Autodesk Fusion 360 part; units mm, degrees
(part 3 of 28)
  line L1276 (49.3387, 32.3207, -1.4859) -> (49.5252, 32.3813, -1.4859)
  line L1277 (49.5252, 32.3813, -1.4859) -> (49.719, 32.412, -1.4859)
  line L1278 (49.719, 32.412, -1.4859) -> (49.9151, 32.412, -1.4859)
  line L1279 (49.9151, 32.412, -1.4859) -> (50.1088, 32.3813, -1.4859)
  line L1280 (111.0688, 32.3813, -1.4859) -> (111.2554, 32.3207, -1.4859)
  line L1281 (111.2554, 32.3207, -1.4859) -> (111.4302, 32.2316, -1.4859)
  line L1282 (111.4302, 32.2316, -1.4859) -> (111.5888, 32.1163, -1.4859)
  line L1283 (111.5888, 32.1163, -1.4859) -> (111.7275, 31.9776, -1.4859)
  line L1284 (111.7275, 31.9776, -1.4859) -> (111.8428, 31.8189, -1.4859)
  line L1285 (111.8428, 31.8189, -1.4859) -> (111.9319, 31.6442, -1.4859)
  line L1286 (111.9319, 31.6442, -1.4859) -> (111.9925, 31.4576, -1.4859)
  line L1287 (111.9925, 31.4576, -1.4859) -> (112.0232, 31.2639, -1.4859)
  line L1288 (112.0232, 31.2639, -1.4859) -> (112.027, 31.1658, -1.4859)
  line L1289 (112.027, 31.1658, -1.4859) -> (112.027, 30.6658, -1.4859)
  line L1290 (112.027, 30.6658, -1.4859) -> (112.0232, 30.5677, -1.4859)
  line L1291 (112.0232, 30.5677, -1.4859) -> (111.9925, 30.374, -1.4859)
  line L1292 (111.9925, 30.374, -1.4859) -> (111.9319, 30.1875, -1.4859)
  line L1293 (111.9319, 30.1875, -1.4859) -> (111.8428, 30.0127, -1.4859)
  line L1294 (111.8428, 30.0127, -1.4859) -> (111.7275, 29.854, -1.4859)
  line L1295 (111.7275, 29.854, -1.4859) -> (111.5888, 29.7153, -1.4859)
  line L1296 (111.5888, 29.7153, -1.4859) -> (111.4302, 29.6, -1.4859)
  line L1297 (111.4302, 29.6, -1.4859) -> (111.2554, 29.511, -1.4859)
  line L1298 (111.2554, 29.511, -1.4859) -> (111.0688, 29.4504, -1.4859)
  line L1299 (111.0688, 29.4504, -1.4859) -> (110.8751, 29.4197, -1.4859)
  line L1300 (110.8751, 29.4197, -1.4859) -> (110.679, 29.4197, -1.4859)
  line L1301 (110.679, 29.4197, -1.4859) -> (110.4852, 29.4504, -1.4859)
  line L1302 (110.4852, 29.4504, -1.4859) -> (110.2987, 29.511, -1.4859)
  line L1303 (110.2987, 29.511, -1.4859) -> (110.1239, 29.6, -1.4859)
  line L1304 (110.1239, 29.6, -1.4859) -> (109.9652, 29.7153, -1.4859)
  line L1305 (109.9652, 29.7153, -1.4859) -> (109.8265, 29.854, -1.4859)
  line L1306 (109.8265, 29.854, -1.4859) -> (109.7112, 30.0127, -1.4859)
  line L1307 (109.7112, 30.0127, -1.4859) -> (109.6222, 30.1875, -1.4859)
  line L1308 (109.6222, 30.1875, -1.4859) -> (109.5616, 30.374, -1.4859)
  line L1309 (109.5616, 30.374, -1.4859) -> (109.5309, 30.5677, -1.4859)
  line L1310 (109.5309, 30.5677, -1.4859) -> (109.527, 30.6658, -1.4859)
  line L1311 (109.527, 30.6658, -1.4859) -> (109.527, 31.1658, -1.4859)
  line L1312 (109.527, 31.1658, -1.4859) -> (109.5309, 31.2639, -1.4859)
  line L1313 (109.5309, 31.2639, -1.4859) -> (109.5616, 31.4576, -1.4859)
  line L1314 (109.5616, 31.4576, -1.4859) -> (109.6222, 31.6442, -1.4859)
  line L1315 (109.6222, 31.6442, -1.4859) -> (109.7112, 31.8189, -1.4859)
  line L1316 (109.7112, 31.8189, -1.4859) -> (109.8265, 31.9776, -1.4859)
  line L1317 (109.8265, 31.9776, -1.4859) -> (109.9652, 32.1163, -1.4859)
  line L1318 (109.9652, 32.1163, -1.4859) -> (110.1239, 32.2316, -1.4859)
  line L1319 (110.1239, 32.2316, -1.4859) -> (110.2987, 32.3207, -1.4859)
  line L1320 (110.2987, 32.3207, -1.4859) -> (110.4852, 32.3813, -1.4859)
  line L1321 (110.4852, 32.3813, -1.4859) -> (110.679, 32.412, -1.4859)
  line L1322 (110.679, 32.412, -1.4859) -> (110.8751, 32.412, -1.4859)
  line L1323 (110.8751, 32.412, -1.4859) -> (111.0688, 32.3813, -1.4859)
  line L1324 (23.2045, 32.6394, -1.4859) -> (23.3177, 32.5841, -1.4859)
  line L1325 (23.3177, 32.5841, -1.4859) -> (23.4069, 32.4949, -1.4859)
  line L1326 (23.4069, 32.4949, -1.4859) -> (23.4622, 32.3817, -1.4859)
  line L1327 (23.4622, 32.3817, -1.4859) -> (23.4781, 32.2725, -1.4859)
  line L1328 (23.4781, 32.2725, -1.4859) -> (23.4781, 30.5881, -1.4859)
  line L1329 (23.4781, 30.5881, -1.4859) -> (23.4622, 30.4789, -1.4859)
  line L1330 (23.4622, 30.4789, -1.4859) -> (23.4069, 30.3657, -1.4859)
  line L1331 (23.4069, 30.3657, -1.4859) -> (23.3177, 30.2766, -1.4859)
  line L1332 (23.3177, 30.2766, -1.4859) -> (23.2045, 30.2212, -1.4859)
  line L1333 (23.2045, 30.2212, -1.4859) -> (23.0953, 30.2053, -1.4859)
  line L1334 (23.0953, 30.2053, -1.4859) -> (20.8609, 30.2053, -1.4859)
  line L1335 (20.8609, 30.2053, -1.4859) -> (20.7517, 30.2212, -1.4859)
  line L1336 (20.7517, 30.2212, -1.4859) -> (20.6385, 30.2766, -1.4859)
  line L1337 (20.6385, 30.2766, -1.4859) -> (20.5494, 30.3657, -1.4859)
  line L1338 (20.5494, 30.3657, -1.4859) -> (20.494, 30.4789, -1.4859)
  line L1339 (20.494, 30.4789, -1.4859) -> (20.4781, 30.5881, -1.4859)
  line L1340 (20.4781, 30.5881, -1.4859) -> (20.4781, 32.2725, -1.4859)
  line L1341 (20.4781, 32.2725, -1.4859) -> (20.494, 32.3817, -1.4859)
  line L1342 (20.494, 32.3817, -1.4859) -> (20.5494, 32.4949, -1.4859)
  line L1343 (20.5494, 32.4949, -1.4859) -> (20.6385, 32.5841, -1.4859)
  line L1344 (20.6385, 32.5841, -1.4859) -> (20.7517, 32.6394, -1.4859)
  line L1345 (20.7517, 32.6394, -1.4859) -> (20.8609, 32.6553, -1.4859)
  line L1346 (20.8609, 32.6553, -1.4859) -> (23.0953, 32.6553, -1.4859)
  line L1347 (23.0953, 32.6553, -1.4859) -> (23.2045, 32.6394, -1.4859)
  line L1348 (84.1645, 32.6394, -1.4859) -> (84.2777, 32.5841, -1.4859)
  line L1349 (84.2777, 32.5841, -1.4859) -> (84.3669, 32.4949, -1.4859)
  line L1350 (84.3669, 32.4949, -1.4859) -> (84.4222, 32.3817, -1.4859)
  line L1351 (84.4222, 32.3817, -1.4859) -> (84.4381, 32.2725, -1.4859)
  line L1352 (84.4381, 32.2725, -1.4859) -> (84.4381, 30.5881, -1.4859)
  line L1353 (84.4381, 30.5881, -1.4859) -> (84.4222, 30.4789, -1.4859)
  line L1354 (84.4222, 30.4789, -1.4859) -> (84.3669, 30.3657, -1.4859)
  line L1355 (84.3669, 30.3657, -1.4859) -> (84.2777, 30.2766, -1.4859)
  line L1356 (84.2777, 30.2766, -1.4859) -> (84.1645, 30.2212, -1.4859)
  line L1357 (84.1645, 30.2212, -1.4859) -> (84.0553, 30.2053, -1.4859)
  line L1358 (84.0553, 30.2053, -1.4859) -> (81.8209, 30.2053, -1.4859)
  line L1359 (81.8209, 30.2053, -1.4859) -> (81.7117, 30.2212, -1.4859)
  line L1360 (81.7117, 30.2212, -1.4859) -> (81.5985, 30.2766, -1.4859)
  line L1361 (81.5985, 30.2766, -1.4859) -> (81.5094, 30.3657, -1.4859)
  line L1362 (81.5094, 30.3657, -1.4859) -> (81.454, 30.4789, -1.4859)
  line L1363 (81.454, 30.4789, -1.4859) -> (81.4381, 30.5881, -1.4859)
  line L1364 (81.4381, 30.5881, -1.4859) -> (81.4381, 32.2725, -1.4859)
  line L1365 (81.4381, 32.2725, -1.4859) -> (81.454, 32.3817, -1.4859)
  line L1366 (81.454, 32.3817, -1.4859) -> (81.5094, 32.4949, -1.4859)
  line L1367 (81.5094, 32.4949, -1.4859) -> (81.5985, 32.5841, -1.4859)
  line L1368 (81.5985, 32.5841, -1.4859) -> (81.7117, 32.6394, -1.4859)
  line L1369 (81.7117, 32.6394, -1.4859) -> (81.8209, 32.6553, -1.4859)
  line L1370 (81.8209, 32.6553, -1.4859) -> (84.0553, 32.6553, -1.4859)
  line L1371 (84.0553, 32.6553, -1.4859) -> (84.1645, 32.6394, -1.4859)
  line L1372 (10.8949, 32.7554, -1.4859) -> (11.0848, 32.7254, -1.4859)
  line L1373 (11.0848, 32.7254, -1.4859) -> (11.2676, 32.666, -1.4859)
  line L1374 (11.2676, 32.666, -1.4859) -> (11.4389, 32.5787, -1.4859)
  line L1375 (11.4389, 32.5787, -1.4859) -> (11.5944, 32.4657, -1.4859)
  line L1376 (11.5944, 32.4657, -1.4859) -> (11.7303, 32.3298, -1.4859)
  line L1377 (11.7303, 32.3298, -1.4859) -> (11.8433, 32.1743, -1.4859)
  line L1378 (11.8433, 32.1743, -1.4859) -> (11.9306, 32.003, -1.4859)
  line L1379 (11.9306, 32.003, -1.4859) -> (11.99, 31.8202, -1.4859)
  line L1380 (11.99, 31.8202, -1.4859) -> (12.0201, 31.6303, -1.4859)
  line L1381 (12.0201, 31.6303, -1.4859) -> (12.0201, 31.4381, -1.4859)
  line L1382 (12.0201, 31.4381, -1.4859) -> (11.99, 31.2482, -1.4859)
  line L1383 (11.99, 31.2482, -1.4859) -> (11.9306, 31.0654, -1.4859)
  line L1384 (11.9306, 31.0654, -1.4859) -> (11.8433, 30.8941, -1.4859)
  line L1385 (11.8433, 30.8941, -1.4859) -> (11.7303, 30.7386, -1.4859)
  line L1386 (11.7303, 30.7386, -1.4859) -> (11.5944, 30.6027, -1.4859)
  line L1387 (11.5944, 30.6027, -1.4859) -> (11.4389, 30.4897, -1.4859)
  line L1388 (11.4389, 30.4897, -1.4859) -> (11.2676, 30.4024, -1.4859)
  line L1389 (11.2676, 30.4024, -1.4859) -> (11.0848, 30.343, -1.4859)
  line L1390 (11.0848, 30.343, -1.4859) -> (10.8949, 30.313, -1.4859)
  line L1391 (10.8949, 30.313, -1.4859) -> (10.7988, 30.3092, -1.4859)
  line L1392 (10.7988, 30.3092, -1.4859) -> (10.2488, 30.3092, -1.4859)
  line L1393 (10.2488, 30.3092, -1.4859) -> (10.1527, 30.313, -1.4859)
  line L1394 (10.1527, 30.313, -1.4859) -> (9.9629, 30.343, -1.4859)
  line L1395 (9.9629, 30.343, -1.4859) -> (9.7801, 30.4024, -1.4859)
  line L1396 (9.7801, 30.4024, -1.4859) -> (9.6088, 30.4897, -1.4859)
  line L1397 (9.6088, 30.4897, -1.4859) -> (9.4533, 30.6027, -1.4859)
  line L1398 (9.4533, 30.6027, -1.4859) -> (9.3173, 30.7386, -1.4859)
  line L1399 (9.3173, 30.7386, -1.4859) -> (9.2044, 30.8941, -1.4859)
  line L1400 (9.2044, 30.8941, -1.4859) -> (9.1171, 31.0654, -1.4859)
  line L1401 (9.1171, 31.0654, -1.4859) -> (9.0577, 31.2482, -1.4859)
  line L1402 (9.0577, 31.2482, -1.4859) -> (9.0276, 31.4381, -1.4859)
  line L1403 (9.0276, 31.4381, -1.4859) -> (9.0276, 31.6303, -1.4859)
  line L1404 (9.0276, 31.6303, -1.4859) -> (9.0577, 31.8202, -1.4859)
  line L1405 (9.0577, 31.8202, -1.4859) -> (9.1171, 32.003, -1.4859)
  line L1406 (9.1171, 32.003, -1.4859) -> (9.2044, 32.1743, -1.4859)
  line L1407 (9.2044, 32.1743, -1.4859) -> (9.3173, 32.3298, -1.4859)
  line L1408 (9.3173, 32.3298, -1.4859) -> (9.4533, 32.4657, -1.4859)
  line L1409 (9.4533, 32.4657, -1.4859) -> (9.6088, 32.5787, -1.4859)
  line L1410 (9.6088, 32.5787, -1.4859) -> (9.7801, 32.666, -1.4859)
  line L1411 (9.7801, 32.666, -1.4859) -> (9.9629, 32.7254, -1.4859)
  line L1412 (9.9629, 32.7254, -1.4859) -> (10.1527, 32.7554, -1.4859)
  line L1413 (10.1527, 32.7554, -1.4859) -> (10.2488, 32.7592, -1.4859)
  line L1414 (10.2488, 32.7592, -1.4859) -> (10.7988, 32.7592, -1.4859)
  line L1415 (10.7988, 32.7592, -1.4859) -> (10.8949, 32.7554, -1.4859)
  line L1416 (71.8549, 32.7554, -1.4859) -> (72.0448, 32.7254, -1.4859)
  line L1417 (72.0448, 32.7254, -1.4859) -> (72.2276, 32.666, -1.4859)
  line L1418 (72.2276, 32.666, -1.4859) -> (72.3989, 32.5787, -1.4859)
  line L1419 (72.3989, 32.5787, -1.4859) -> (72.5544, 32.4657, -1.4859)
  line L1420 (72.5544, 32.4657, -1.4859) -> (72.6903, 32.3298, -1.4859)
  line L1421 (72.6903, 32.3298, -1.4859) -> (72.8033, 32.1743, -1.4859)
  line L1422 (72.8033, 32.1743, -1.4859) -> (72.8906, 32.003, -1.4859)
  line L1423 (72.8906, 32.003, -1.4859) -> (72.95, 31.8202, -1.4859)
  line L1424 (72.95, 31.8202, -1.4859) -> (72.9801, 31.6303, -1.4859)
  line L1425 (72.9801, 31.6303, -1.4859) -> (72.9801, 31.4381, -1.4859)
  line L1426 (72.9801, 31.4381, -1.4859) -> (72.95, 31.2482, -1.4859)
  line L1427 (72.95, 31.2482, -1.4859) -> (72.8906, 31.0654, -1.4859)
  line L1428 (72.8906, 31.0654, -1.4859) -> (72.8033, 30.8941, -1.4859)
  line L1429 (72.8033, 30.8941, -1.4859) -> (72.6903, 30.7386, -1.4859)
  line L1430 (72.6903, 30.7386, -1.4859) -> (72.5544, 30.6027, -1.4859)
  line L1431 (72.5544, 30.6027, -1.4859) -> (72.3989, 30.4897, -1.4859)
  line L1432 (72.3989, 30.4897, -1.4859) -> (72.2276, 30.4024, -1.4859)
  line L1433 (72.2276, 30.4024, -1.4859) -> (72.0448, 30.343, -1.4859)
  line L1434 (72.0448, 30.343, -1.4859) -> (71.8549, 30.313, -1.4859)
  line L1435 (71.8549, 30.313, -1.4859) -> (71.7588, 30.3092, -1.4859)
  line L1436 (71.7588, 30.3092, -1.4859) -> (71.2088, 30.3092, -1.4859)
  line L1437 (71.2088, 30.3092, -1.4859) -> (71.1127, 30.313, -1.4859)
  line L1438 (71.1127, 30.313, -1.4859) -> (70.9229, 30.343, -1.4859)
  line L1439 (70.9229, 30.343, -1.4859) -> (70.7401, 30.4024, -1.4859)
  line L1440 (70.7401, 30.4024, -1.4859) -> (70.5688, 30.4897, -1.4859)
  line L1441 (70.5688, 30.4897, -1.4859) -> (70.4133, 30.6027, -1.4859)
  line L1442 (70.4133, 30.6027, -1.4859) -> (70.2773, 30.7386, -1.4859)
  line L1443 (70.2773, 30.7386, -1.4859) -> (70.1644, 30.8941, -1.4859)
  line L1444 (70.1644, 30.8941, -1.4859) -> (70.0771, 31.0654, -1.4859)
  line L1445 (70.0771, 31.0654, -1.4859) -> (70.0177, 31.2482, -1.4859)
  line L1446 (70.0177, 31.2482, -1.4859) -> (69.9876, 31.4381, -1.4859)
  line L1447 (69.9876, 31.4381, -1.4859) -> (69.9876, 31.6303, -1.4859)
  line L1448 (69.9876, 31.6303, -1.4859) -> (70.0177, 31.8202, -1.4859)
  line L1449 (70.0177, 31.8202, -1.4859) -> (70.0771, 32.003, -1.4859)
  line L1450 (70.0771, 32.003, -1.4859) -> (70.1644, 32.1743, -1.4859)
  line L1451 (70.1644, 32.1743, -1.4859) -> (70.2773, 32.3298, -1.4859)
  line L1452 (70.2773, 32.3298, -1.4859) -> (70.4133, 32.4657, -1.4859)
  line L1453 (70.4133, 32.4657, -1.4859) -> (70.5688, 32.5787, -1.4859)
  line L1454 (70.5688, 32.5787, -1.4859) -> (70.7401, 32.666, -1.4859)
  line L1455 (70.7401, 32.666, -1.4859) -> (70.9229, 32.7254, -1.4859)
  line L1456 (70.9229, 32.7254, -1.4859) -> (71.1127, 32.7554, -1.4859)
  line L1457 (71.1127, 32.7554, -1.4859) -> (71.2088, 32.7592, -1.4859)
  line L1458 (71.2088, 32.7592, -1.4859) -> (71.7588, 32.7592, -1.4859)
  line L1459 (71.7588, 32.7592, -1.4859) -> (71.8549, 32.7554, -1.4859)
  line L1460 (44.7235, 30.6535, -1.4859) -> (41.5235, 30.6535, -1.4859)
  line L1461 (41.5235, 30.6535, -1.4859) -> (41.5235, 32.6535, -1.4859)
  line L1462 (41.5235, 32.6535, -1.4859) -> (44.7235, 32.6535, -1.4859)
  line L1463 (44.7235, 32.6535, -1.4859) -> (44.7235, 30.6535, -1.4859)
  line L1464 (105.6835, 30.6535, -1.4859) -> (102.4835, 30.6535, -1.4859)
  line L1465 (102.4835, 30.6535, -1.4859) -> (102.4835, 32.6535, -1.4859)
  line L1466 (102.4835, 32.6535, -1.4859) -> (105.6835, 32.6535, -1.4859)
  line L1467 (105.6835, 32.6535, -1.4859) -> (105.6835, 30.6535, -1.4859)
  line L1468 (32.9849, 70.1522, -1.4859) -> (33.1714, 70.0916, -1.4859)
  line L1469 (33.1714, 70.0916, -1.4859) -> (33.3462, 70.0025, -1.4859)
  line L1470 (33.3462, 70.0025, -1.4859) -> (33.5049, 69.8872, -1.4859)
  line L1471 (33.5049, 69.8872, -1.4859) -> (33.6436, 69.7485, -1.4859)
  line L1472 (33.6436, 69.7485, -1.4859) -> (33.7588, 69.5899, -1.4859)
  line L1473 (33.7588, 69.5899, -1.4859) -> (33.8479, 69.4151, -1.4859)
  line L1474 (33.8479, 69.4151, -1.4859) -> (33.9085, 69.2285, -1.4859)
  line L1475 (33.9085, 69.2285, -1.4859) -> (33.9392, 69.0348, -1.4859)
  line L1476 (33.9392, 69.0348, -1.4859) -> (33.943, 68.9367, -1.4859)
  line L1477 (33.943, 68.9367, -1.4859) -> (33.943, 68.4367, -1.4859)
  line L1478 (33.943, 68.4367, -1.4859) -> (33.9392, 68.3387, -1.4859)
  line L1479 (33.9392, 68.3387, -1.4859) -> (33.9085, 68.1449, -1.4859)
  line L1480 (33.9085, 68.1449, -1.4859) -> (33.8479, 67.9584, -1.4859)
  line L1481 (33.8479, 67.9584, -1.4859) -> (33.7588, 67.7836, -1.4859)
  line L1482 (33.7588, 67.7836, -1.4859) -> (33.6436, 67.6249, -1.4859)
  line L1483 (33.6436, 67.6249, -1.4859) -> (33.5049, 67.4862, -1.4859)
  line L1484 (33.5049, 67.4862, -1.4859) -> (33.3462, 67.3709, -1.4859)
  line L1485 (33.3462, 67.3709, -1.4859) -> (33.1714, 67.2819, -1.4859)
  line L1486 (33.1714, 67.2819, -1.4859) -> (32.9848, 67.2213, -1.4859)
  line L1487 (32.9848, 67.2213, -1.4859) -> (32.7911, 67.1906, -1.4859)
  line L1488 (32.7911, 67.1906, -1.4859) -> (32.595, 67.1906, -1.4859)
  line L1489 (32.595, 67.1906, -1.4859) -> (32.4012, 67.2213, -1.4859)
  line L1490 (32.4012, 67.2213, -1.4859) -> (32.2147, 67.2819, -1.4859)
  line L1491 (32.2147, 67.2819, -1.4859) -> (32.163, 67.3082, -1.4859)
  line L1492 (32.163, 67.3082, -1.4859) -> (28.5773, 63.7225, -1.4859)
  line L1493 (28.5773, 63.7225, -1.4859) -> (28.5183, 63.6708, -1.4859)
  line L1494 (28.5183, 63.6708, -1.4859) -> (28.3827, 63.5924, -1.4859)
  line L1495 (28.3827, 63.5924, -1.4859) -> (28.2314, 63.5519, -1.4859)
  line L1496 (28.2314, 63.5519, -1.4859) -> (28.1531, 63.5468, -1.4859)
  line L1497 (28.1531, 63.5468, -1.4859) -> (25.1258, 63.5468, -1.4859)
  line L1498 (25.1258, 63.5468, -1.4859) -> (25.0987, 63.4936, -1.4859)
  line L1499 (25.0987, 63.4936, -1.4859) -> (24.9834, 63.335, -1.4859)
  line L1500 (24.9834, 63.335, -1.4859) -> (24.8447, 63.1963, -1.4859)
  line L1501 (24.8447, 63.1963, -1.4859) -> (24.686, 63.081, -1.4859)
  line L1502 (24.686, 63.081, -1.4859) -> (24.5112, 62.9919, -1.4859)
  line L1503 (24.5112, 62.9919, -1.4859) -> (24.3829, 62.9502, -1.4859)
  line L1504 (24.3829, 62.9502, -1.4859) -> (24.3829, 59.6133, -1.4859)
  line L1505 (24.3829, 59.6133, -1.4859) -> (24.3778, 59.535, -1.4859)
  line L1506 (24.3778, 59.535, -1.4859) -> (24.3372, 59.3837, -1.4859)
  line L1507 (24.3372, 59.3837, -1.4859) -> (24.2589, 59.2481, -1.4859)
  line L1508 (24.2589, 59.2481, -1.4859) -> (24.2072, 59.1891, -1.4859)
  line L1509 (24.2072, 59.1891, -1.4859) -> (20.6569, 55.6388, -1.4859)
  line L1510 (20.6569, 55.6388, -1.4859) -> (20.6569, 46.29, -1.4859)
  line L1511 (20.6569, 46.29, -1.4859) -> (20.6518, 46.2116, -1.4859)
  line L1512 (20.6518, 46.2116, -1.4859) -> (20.6113, 46.0604, -1.4859)
  line L1513 (20.6113, 46.0604, -1.4859) -> (20.5329, 45.9247, -1.4859)
  line L1514 (20.5329, 45.9247, -1.4859) -> (20.4812, 45.8657, -1.4859)
  line L1515 (20.4812, 45.8657, -1.4859) -> (17.2658, 42.6503, -1.4859)
  line L1516 (17.2658, 42.6503, -1.4859) -> (17.2658, 40.7738, -1.4859)
  line L1517 (17.2658, 40.7738, -1.4859) -> (14.8158, 40.7738, -1.4859)
  line L1518 (14.8158, 40.7738, -1.4859) -> (14.8158, 43.7738, -1.4859)
  line L1519 (14.8158, 43.7738, -1.4859) -> (16.6923, 43.7738, -1.4859)
  line L1520 (16.6923, 43.7738, -1.4859) -> (19.4569, 46.5385, -1.4859)
  line L1521 (19.4569, 46.5385, -1.4859) -> (19.4569, 55.8874, -1.4859)
  line L1522 (19.4569, 55.8874, -1.4859) -> (19.4621, 55.9657, -1.4859)
  line L1523 (19.4621, 55.9657, -1.4859) -> (19.5026, 56.117, -1.4859)
  line L1524 (19.5026, 56.117, -1.4859) -> (19.5809, 56.2526, -1.4859)
  line L1525 (19.5809, 56.2526, -1.4859) -> (19.6327, 56.3116, -1.4859)
  line L1526 (19.6327, 56.3116, -1.4859) -> (23.1829, 59.8619, -1.4859)
  line L1527 (23.1829, 59.8619, -1.4859) -> (23.1829, 62.9502, -1.4859)
  line L1528 (23.1829, 62.9502, -1.4859) -> (23.0545, 62.9919, -1.4859)
  line L1529 (23.0545, 62.9919, -1.4859) -> (22.8798, 63.081, -1.4859)
  line L1530 (22.8798, 63.081, -1.4859) -> (22.7211, 63.1963, -1.4859)
  line L1531 (22.7211, 63.1963, -1.4859) -> (22.5824, 63.335, -1.4859)
  line L1532 (22.5824, 63.335, -1.4859) -> (22.4671, 63.4936, -1.4859)
  line L1533 (22.4671, 63.4936, -1.4859) -> (22.378, 63.6684, -1.4859)
  line L1534 (22.378, 63.6684, -1.4859) -> (22.3174, 63.855, -1.4859)
  line L1535 (22.3174, 63.855, -1.4859) -> (22.2867, 64.0487, -1.4859)
  line L1536 (22.2867, 64.0487, -1.4859) -> (22.2867, 64.2448, -1.4859)
  line L1537 (22.2867, 64.2448, -1.4859) -> (22.3174, 64.4386, -1.4859)
  line L1538 (22.3174, 64.4386, -1.4859) -> (22.378, 64.6251, -1.4859)
  line L1539 (22.378, 64.6251, -1.4859) -> (22.4671, 64.7999, -1.4859)
  line L1540 (22.4671, 64.7999, -1.4859) -> (22.5824, 64.9586, -1.4859)
  line L1541 (22.5824, 64.9586, -1.4859) -> (22.7211, 65.0973, -1.4859)
  line L1542 (22.7211, 65.0973, -1.4859) -> (22.8798, 65.2126, -1.4859)
  line L1543 (22.8798, 65.2126, -1.4859) -> (23.0545, 65.3016, -1.4859)
  line L1544 (23.0545, 65.3016, -1.4859) -> (23.2411, 65.3622, -1.4859)
  line L1545 (23.2411, 65.3622, -1.4859) -> (23.4348, 65.3929, -1.4859)
  line L1546 (23.4348, 65.3929, -1.4859) -> (23.5329, 65.3968, -1.4859)
  line L1547 (23.5329, 65.3968, -1.4859) -> (24.0329, 65.3968, -1.4859)
  line L1548 (24.0329, 65.3968, -1.4859) -> (24.131, 65.3929, -1.4859)
  line L1549 (24.131, 65.3929, -1.4859) -> (24.3247, 65.3622, -1.4859)
  line L1550 (24.3247, 65.3622, -1.4859) -> (24.5112, 65.3016, -1.4859)
  line L1551 (24.5112, 65.3016, -1.4859) -> (24.686, 65.2126, -1.4859)
  line L1552 (24.686, 65.2126, -1.4859) -> (24.8447, 65.0973, -1.4859)
  line L1553 (24.8447, 65.0973, -1.4859) -> (24.9834, 64.9586, -1.4859)
  line L1554 (24.9834, 64.9586, -1.4859) -> (25.0987, 64.7999, -1.4859)
  line L1555 (25.0987, 64.7999, -1.4859) -> (25.1258, 64.7468, -1.4859)
  line L1556 (25.1258, 64.7468, -1.4859) -> (27.9045, 64.7468, -1.4859)
  line L1557 (27.9045, 64.7468, -1.4859) -> (31.4537, 68.2959, -1.4859)
  line L1558 (31.4537, 68.2959, -1.4859) -> (31.4469, 68.3387, -1.4859)
  line L1559 (31.4469, 68.3387, -1.4859) -> (31.443, 68.4367, -1.4859)
  line L1560 (31.443, 68.4367, -1.4859) -> (31.443, 68.9367, -1.4859)
  line L1561 (31.443, 68.9367, -1.4859) -> (31.4469, 69.0348, -1.4859)
  line L1562 (31.4469, 69.0348, -1.4859) -> (31.4776, 69.2285, -1.4859)
  line L1563 (31.4776, 69.2285, -1.4859) -> (31.5382, 69.4151, -1.4859)
  line L1564 (31.5382, 69.4151, -1.4859) -> (31.6272, 69.5899, -1.4859)
  line L1565 (31.6272, 69.5899, -1.4859) -> (31.7425, 69.7485, -1.4859)
  line L1566 (31.7425, 69.7485, -1.4859) -> (31.8812, 69.8872, -1.4859)
  line L1567 (31.8812, 69.8872, -1.4859) -> (32.0399, 70.0025, -1.4859)
  line L1568 (32.0399, 70.0025, -1.4859) -> (32.2147, 70.0916, -1.4859)
  line L1569 (32.2147, 70.0916, -1.4859) -> (32.4012, 70.1522, -1.4859)
  line L1570 (32.4012, 70.1522, -1.4859) -> (32.595, 70.1829, -1.4859)
  line L1571 (32.595, 70.1829, -1.4859) -> (32.7911, 70.1829, -1.4859)
  line L1572 (32.7911, 70.1829, -1.4859) -> (32.9848, 70.1522, -1.4859)
  line L1573 (67.9098, 70.1522, -1.4859) -> (68.0964, 70.0916, -1.4859)
  line L1574 (68.0964, 70.0916, -1.4859) -> (68.2712, 70.0025, -1.4859)
  line L1575 (68.2712, 70.0025, -1.4859) -> (68.4299, 69.8872, -1.4859)
  line L1576 (68.4299, 69.8872, -1.4859) -> (68.5686, 69.7485, -1.4859)
  line L1577 (68.5685, 69.7485, -1.4859) -> (68.6838, 69.5899, -1.4859)
  line L1578 (68.6838, 69.5899, -1.4859) -> (68.7729, 69.4151, -1.4859)
  line L1579 (68.7729, 69.4151, -1.4859) -> (68.8335, 69.2285, -1.4859)
  line L1580 (68.8335, 69.2285, -1.4859) -> (68.8642, 69.0348, -1.4859)
  line L1581 (68.8642, 69.0348, -1.4859) -> (68.868, 68.9367, -1.4859)
  line L1582 (68.868, 68.9367, -1.4859) -> (68.868, 68.4367, -1.4859)
  line L1583 (68.868, 68.4367, -1.4859) -> (68.8642, 68.3387, -1.4859)
  line L1584 (68.8642, 68.3387, -1.4859) -> (68.8335, 68.1449, -1.4859)
  line L1585 (68.8335, 68.1449, -1.4859) -> (68.7729, 67.9584, -1.4859)
  line L1586 (68.7729, 67.9584, -1.4859) -> (68.6838, 67.7836, -1.4859)
  line L1587 (68.6838, 67.7836, -1.4859) -> (68.5686, 67.6249, -1.4859)
  line L1588 (68.5685, 67.6249, -1.4859) -> (68.4299, 67.4862, -1.4859)
  line L1589 (68.4299, 67.4862, -1.4859) -> (68.2712, 67.3709, -1.4859)
  line L1590 (68.2712, 67.3709, -1.4859) -> (68.0964, 67.2819, -1.4859)
  line L1591 (68.0964, 67.2819, -1.4859) -> (67.9099, 67.2213, -1.4859)
  line L1592 (67.9098, 67.2213, -1.4859) -> (67.7161, 67.1906, -1.4859)
  line L1593 (67.7161, 67.1906, -1.4859) -> (67.52, 67.1906, -1.4859)
  line L1594 (67.52, 67.1906, -1.4859) -> (67.3262, 67.2213, -1.4859)
  line L1595 (67.3262, 67.2213, -1.4859) -> (67.1397, 67.2819, -1.4859)
  line L1596 (67.1397, 67.2819, -1.4859) -> (67.088, 67.3082, -1.4859)
  line L1597 (67.088, 67.3082, -1.4859) -> (63.5023, 63.7225, -1.4859)
  line L1598 (63.5023, 63.7225, -1.4859) -> (63.4433, 63.6708, -1.4859)
  line L1599 (63.4433, 63.6708, -1.4859) -> (63.3077, 63.5924, -1.4859)
  line L1600 (63.3077, 63.5924, -1.4859) -> (63.1564, 63.5519, -1.4859)
  line L1601 (63.1564, 63.5519, -1.4859) -> (63.0781, 63.5468, -1.4859)
  line L1602 (63.0781, 63.5468, -1.4859) -> (60.0508, 63.5468, -1.4859)
  line L1603 (60.0508, 63.5468, -1.4859) -> (60.0237, 63.4936, -1.4859)
  line L1604 (60.0237, 63.4936, -1.4859) -> (59.9084, 63.335, -1.4859)
  line L1605 (59.9084, 63.335, -1.4859) -> (59.7697, 63.1963, -1.4859)
  line L1606 (59.7697, 63.1963, -1.4859) -> (59.611, 63.081, -1.4859)
  line L1607 (59.611, 63.081, -1.4859) -> (59.4362, 62.9919, -1.4859)
  line L1608 (59.4362, 62.9919, -1.4859) -> (59.3079, 62.9502, -1.4859)
  line L1609 (59.3079, 62.9502, -1.4859) -> (59.3079, 59.6133, -1.4859)
  line L1610 (59.3079, 59.6133, -1.4859) -> (59.3028, 59.535, -1.4859)
  line L1611 (59.3028, 59.535, -1.4859) -> (59.2622, 59.3837, -1.4859)
  line L1612 (59.2622, 59.3837, -1.4859) -> (59.1839, 59.2481, -1.4859)
  line L1613 (59.1839, 59.2481, -1.4859) -> (59.1322, 59.1891, -1.4859)
  line L1614 (59.1322, 59.1891, -1.4859) -> (55.5819, 55.6388, -1.4859)
  line L1615 (55.5819, 55.6388, -1.4859) -> (55.5819, 46.29, -1.4859)
  line L1616 (55.5819, 46.29, -1.4859) -> (55.5768, 46.2116, -1.4859)
  line L1617 (55.5768, 46.2116, -1.4859) -> (55.5363, 46.0604, -1.4859)
  line L1618 (55.5363, 46.0604, -1.4859) -> (55.4579, 45.9247, -1.4859)
  line L1619 (55.4579, 45.9247, -1.4859) -> (55.4062, 45.8657, -1.4859)
  line L1620 (55.4062, 45.8657, -1.4859) -> (52.1908, 42.6503, -1.4859)
  line L1621 (52.1908, 42.6503, -1.4859) -> (52.1908, 40.7738, -1.4859)
  line L1622 (52.1908, 40.7738, -1.4859) -> (49.7408, 40.7738, -1.4859)
  line L1623 (49.7408, 40.7738, -1.4859) -> (49.7408, 43.7738, -1.4859)
  line L1624 (49.7408, 43.7738, -1.4859) -> (51.6173, 43.7738, -1.4859)
  line L1625 (51.6173, 43.7738, -1.4859) -> (54.3819, 46.5385, -1.4859)
  line L1626 (54.3819, 46.5385, -1.4859) -> (54.3819, 55.8874, -1.4859)
  line L1627 (54.3819, 55.8874, -1.4859) -> (54.3871, 55.9657, -1.4859)
  line L1628 (54.3871, 55.9657, -1.4859) -> (54.4276, 56.117, -1.4859)
  line L1629 (54.4276, 56.117, -1.4859) -> (54.5059, 56.2526, -1.4859)
  line L1630 (54.5059, 56.2526, -1.4859) -> (54.5577, 56.3116, -1.4859)
  line L1631 (54.5577, 56.3116, -1.4859) -> (58.1079, 59.8619, -1.4859)
  line L1632 (58.1079, 59.8619, -1.4859) -> (58.1079, 62.9502, -1.4859)
  line L1633 (58.1079, 62.9502, -1.4859) -> (57.9795, 62.9919, -1.4859)
  line L1634 (57.9795, 62.9919, -1.4859) -> (57.8048, 63.081, -1.4859)
  line L1635 (57.8048, 63.081, -1.4859) -> (57.6461, 63.1963, -1.4859)
  line L1636 (57.6461, 63.1963, -1.4859) -> (57.5074, 63.335, -1.4859)
  line L1637 (57.5074, 63.335, -1.4859) -> (57.3921, 63.4936, -1.4859)
  line L1638 (57.3921, 63.4936, -1.4859) -> (57.303, 63.6684, -1.4859)
  line L1639 (57.303, 63.6684, -1.4859) -> (57.2424, 63.855, -1.4859)
  line L1640 (57.2424, 63.855, -1.4859) -> (57.2117, 64.0487, -1.4859)
  line L1641 (57.2117, 64.0487, -1.4859) -> (57.2117, 64.2448, -1.4859)
  line L1642 (57.2117, 64.2448, -1.4859) -> (57.2424, 64.4386, -1.4859)
  line L1643 (57.2424, 64.4386, -1.4859) -> (57.303, 64.6251, -1.4859)
  line L1644 (57.303, 64.6251, -1.4859) -> (57.3921, 64.7999, -1.4859)
  line L1645 (57.3921, 64.7999, -1.4859) -> (57.5074, 64.9586, -1.4859)
  line L1646 (57.5074, 64.9586, -1.4859) -> (57.6461, 65.0973, -1.4859)
  line L1647 (57.6461, 65.0973, -1.4859) -> (57.8048, 65.2126, -1.4859)
  line L1648 (57.8048, 65.2126, -1.4859) -> (57.9795, 65.3016, -1.4859)
  line L1649 (57.9795, 65.3016, -1.4859) -> (58.1661, 65.3622, -1.4859)
  line L1650 (58.1661, 65.3622, -1.4859) -> (58.3598, 65.3929, -1.4859)
  line L1651 (58.3598, 65.3929, -1.4859) -> (58.4579, 65.3968, -1.4859)
  line L1652 (58.4579, 65.3968, -1.4859) -> (58.9579, 65.3968, -1.4859)
  line L1653 (58.9579, 65.3968, -1.4859) -> (59.056, 65.3929, -1.4859)
  line L1654 (59.056, 65.3929, -1.4859) -> (59.2497, 65.3622, -1.4859)
  line L1655 (59.2497, 65.3622, -1.4859) -> (59.4362, 65.3016, -1.4859)
  line L1656 (59.4362, 65.3016, -1.4859) -> (59.611, 65.2126, -1.4859)
  line L1657 (59.611, 65.2126, -1.4859) -> (59.7697, 65.0973, -1.4859)
  line L1658 (59.7697, 65.0973, -1.4859) -> (59.9084, 64.9586, -1.4859)
  line L1659 (59.9084, 64.9586, -1.4859) -> (60.0237, 64.7999, -1.4859)
  line L1660 (60.0237, 64.7999, -1.4859) -> (60.0508, 64.7468, -1.4859)
  line L1661 (60.0508, 64.7468, -1.4859) -> (62.8295, 64.7468, -1.4859)
  line L1662 (62.8295, 64.7468, -1.4859) -> (66.3787, 68.2959, -1.4859)
  line L1663 (66.3787, 68.2959, -1.4859) -> (66.3719, 68.3387, -1.4859)
  line L1664 (66.3719, 68.3387, -1.4859) -> (66.368, 68.4367, -1.4859)
  line L1665 (66.368, 68.4367, -1.4859) -> (66.368, 68.9367, -1.4859)
  line L1666 (66.368, 68.9367, -1.4859) -> (66.3719, 69.0348, -1.4859)
  line L1667 (66.3719, 69.0348, -1.4859) -> (66.4026, 69.2285, -1.4859)
  line L1668 (66.4026, 69.2285, -1.4859) -> (66.4632, 69.4151, -1.4859)
  line L1669 (66.4632, 69.4151, -1.4859) -> (66.5522, 69.5899, -1.4859)
  line L1670 (66.5522, 69.5899, -1.4859) -> (66.6675, 69.7485, -1.4859)
  line L1671 (66.6675, 69.7485, -1.4859) -> (66.8062, 69.8872, -1.4859)
  line L1672 (66.8062, 69.8872, -1.4859) -> (66.9649, 70.0025, -1.4859)
  line L1673 (66.9649, 70.0025, -1.4859) -> (67.1397, 70.0916, -1.4859)
  line L1674 (67.1397, 70.0916, -1.4859) -> (67.3262, 70.1522, -1.4859)
  line L1675 (67.3262, 70.1522, -1.4859) -> (67.52, 70.1829, -1.4859)
  line L1676 (67.52, 70.1829, -1.4859) -> (67.7161, 70.1829, -1.4859)
  line L1677 (67.7161, 70.1829, -1.4859) -> (67.9098, 70.1522, -1.4859)
  line L1678 (102.8349, 70.1522, -1.4859) -> (103.0214, 70.0916, -1.4859)
  line L1679 (103.0214, 70.0916, -1.4859) -> (103.1962, 70.0025, -1.4859)
  line L1680 (103.1962, 70.0025, -1.4859) -> (103.3549, 69.8872, -1.4859)
  line L1681 (103.3549, 69.8872, -1.4859) -> (103.4936, 69.7485, -1.4859)
  line L1682 (103.4936, 69.7485, -1.4859) -> (103.6088, 69.5899, -1.4859)
  line L1683 (103.6088, 69.5899, -1.4859) -> (103.6979, 69.4151, -1.4859)
  line L1684 (103.6979, 69.4151, -1.4859) -> (103.7585, 69.2285, -1.4859)
  line L1685 (103.7585, 69.2285, -1.4859) -> (103.7892, 69.0348, -1.4859)
  line L1686 (103.7892, 69.0348, -1.4859) -> (103.793, 68.9367, -1.4859)
  line L1687 (103.793, 68.9367, -1.4859) -> (103.793, 68.4367, -1.4859)
  line L1688 (103.793, 68.4367, -1.4859) -> (103.7892, 68.3387, -1.4859)
  line L1689 (103.7892, 68.3387, -1.4859) -> (103.7585, 68.1449, -1.4859)
  line L1690 (103.7585, 68.1449, -1.4859) -> (103.6979, 67.9584, -1.4859)
  line L1691 (103.6979, 67.9584, -1.4859) -> (103.6088, 67.7836, -1.4859)
  line L1692 (103.6088, 67.7836, -1.4859) -> (103.4936, 67.6249, -1.4859)
  line L1693 (103.4936, 67.6249, -1.4859) -> (103.3549, 67.4862, -1.4859)
  line L1694 (103.3549, 67.4862, -1.4859) -> (103.1962, 67.3709, -1.4859)
  line L1695 (103.1962, 67.3709, -1.4859) -> (103.0214, 67.2819, -1.4859)
  line L1696 (103.0214, 67.2819, -1.4859) -> (102.8349, 67.2213, -1.4859)
  line L1697 (102.8349, 67.2213, -1.4859) -> (102.6411, 67.1906, -1.4859)
  line L1698 (102.6411, 67.1906, -1.4859) -> (102.445, 67.1906, -1.4859)
  line L1699 (102.445, 67.1906, -1.4859) -> (102.2512, 67.2213, -1.4859)
  line L1700 (102.2512, 67.2213, -1.4859) -> (102.0647, 67.2819, -1.4859)
  line L1701 (102.0647, 67.2819, -1.4859) -> (102.013, 67.3082, -1.4859)
  line L1702 (102.013, 67.3082, -1.4859) -> (98.4273, 63.7225, -1.4859)
  line L1703 (98.4273, 63.7225, -1.4859) -> (98.3683, 63.6708, -1.4859)
  line L1704 (98.3683, 63.6708, -1.4859) -> (98.2327, 63.5924, -1.4859)
  line L1705 (98.2327, 63.5924, -1.4859) -> (98.0814, 63.5519, -1.4859)
  line L1706 (98.0814, 63.5519, -1.4859) -> (98.0031, 63.5468, -1.4859)
  line L1707 (98.0031, 63.5468, -1.4859) -> (94.9758, 63.5468, -1.4859)
  line L1708 (94.9758, 63.5468, -1.4859) -> (94.9487, 63.4936, -1.4859)
  line L1709 (94.9487, 63.4936, -1.4859) -> (94.8334, 63.335, -1.4859)
  line L1710 (94.8334, 63.335, -1.4859) -> (94.6947, 63.1963, -1.4859)
  line L1711 (94.6947, 63.1963, -1.4859) -> (94.536, 63.081, -1.4859)
  line L1712 (94.536, 63.081, -1.4859) -> (94.3612, 62.9919, -1.4859)
  line L1713 (94.3612, 62.9919, -1.4859) -> (94.2329, 62.9502, -1.4859)
  line L1714 (94.2329, 62.9502, -1.4859) -> (94.2329, 59.6133, -1.4859)
  line L1715 (94.2329, 59.6133, -1.4859) -> (94.2278, 59.535, -1.4859)
  line L1716 (94.2278, 59.535, -1.4859) -> (94.1872, 59.3837, -1.4859)
  line L1717 (94.1872, 59.3837, -1.4859) -> (94.1089, 59.2481, -1.4859)
  line L1718 (94.1089, 59.2481, -1.4859) -> (94.0572, 59.1891, -1.4859)
  line L1719 (94.0572, 59.1891, -1.4859) -> (90.5069, 55.6388, -1.4859)
  line L1720 (90.5069, 55.6388, -1.4859) -> (90.5069, 46.29, -1.4859)
  line L1721 (90.5069, 46.29, -1.4859) -> (90.5018, 46.2116, -1.4859)
  line L1722 (90.5018, 46.2116, -1.4859) -> (90.4613, 46.0604, -1.4859)
  line L1723 (90.4613, 46.0604, -1.4859) -> (90.3829, 45.9247, -1.4859)
  line L1724 (90.3829, 45.9247, -1.4859) -> (90.3312, 45.8657, -1.4859)
  line L1725 (90.3312, 45.8657, -1.4859) -> (87.1158, 42.6503, -1.4859)
  line L1726 (87.1158, 42.6503, -1.4859) -> (87.1158, 40.7738, -1.4859)
  line L1727 (87.1158, 40.7738, -1.4859) -> (84.6658, 40.7738, -1.4859)
  line L1728 (84.6658, 40.7738, -1.4859) -> (84.6658, 43.7738, -1.4859)
  line L1729 (84.6658, 43.7738, -1.4859) -> (86.5423, 43.7738, -1.4859)
  line L1730 (86.5423, 43.7738, -1.4859) -> (89.3069, 46.5385, -1.4859)
  line L1731 (89.3069, 46.5385, -1.4859) -> (89.3069, 55.8874, -1.4859)
  line L1732 (89.3069, 55.8874, -1.4859) -> (89.3121, 55.9657, -1.4859)
  line L1733 (89.3121, 55.9657, -1.4859) -> (89.3526, 56.117, -1.4859)
  line L1734 (89.3526, 56.117, -1.4859) -> (89.4309, 56.2526, -1.4859)
  line L1735 (89.4309, 56.2526, -1.4859) -> (89.4827, 56.3116, -1.4859)
  line L1736 (89.4827, 56.3116, -1.4859) -> (93.0329, 59.8619, -1.4859)
  line L1737 (93.0329, 59.8619, -1.4859) -> (93.0329, 62.9502, -1.4859)
  line L1738 (93.0329, 62.9502, -1.4859) -> (92.9045, 62.9919, -1.4859)
  line L1739 (92.9045, 62.9919, -1.4859) -> (92.7298, 63.081, -1.4859)
  line L1740 (92.7298, 63.081, -1.4859) -> (92.5711, 63.1963, -1.4859)
  line L1741 (92.5711, 63.1963, -1.4859) -> (92.4324, 63.335, -1.4859)
  line L1742 (92.4324, 63.335, -1.4859) -> (92.3171, 63.4936, -1.4859)
  line L1743 (92.3171, 63.4936, -1.4859) -> (92.228, 63.6684, -1.4859)
  line L1744 (92.228, 63.6684, -1.4859) -> (92.1674, 63.855, -1.4859)
  line L1745 (92.1674, 63.855, -1.4859) -> (92.1367, 64.0487, -1.4859)
  line L1746 (92.1367, 64.0487, -1.4859) -> (92.1367, 64.2448, -1.4859)
  line L1747 (92.1367, 64.2448, -1.4859) -> (92.1674, 64.4386, -1.4859)
  line L1748 (92.1674, 64.4386, -1.4859) -> (92.228, 64.6251, -1.4859)
  line L1749 (92.228, 64.6251, -1.4859) -> (92.3171, 64.7999, -1.4859)
  line L1750 (92.3171, 64.7999, -1.4859) -> (92.4324, 64.9586, -1.4859)
  line L1751 (92.4324, 64.9586, -1.4859) -> (92.5711, 65.0973, -1.4859)
  line L1752 (92.5711, 65.0973, -1.4859) -> (92.7298, 65.2126, -1.4859)
  line L1753 (92.7298, 65.2126, -1.4859) -> (92.9045, 65.3016, -1.4859)
  line L1754 (92.9045, 65.3016, -1.4859) -> (93.0911, 65.3622, -1.4859)
  line L1755 (93.0911, 65.3622, -1.4859) -> (93.2848, 65.3929, -1.4859)
  line L1756 (93.2848, 65.3929, -1.4859) -> (93.3829, 65.3968, -1.4859)
  line L1757 (93.3829, 65.3968, -1.4859) -> (93.8829, 65.3968, -1.4859)
  line L1758 (93.8829, 65.3968, -1.4859) -> (93.981, 65.3929, -1.4859)
  line L1759 (93.981, 65.3929, -1.4859) -> (94.1747, 65.3622, -1.4859)
  line L1760 (94.1747, 65.3622, -1.4859) -> (94.3612, 65.3016, -1.4859)
  line L1761 (94.3612, 65.3016, -1.4859) -> (94.536, 65.2126, -1.4859)
  line L1762 (94.536, 65.2126, -1.4859) -> (94.6947, 65.0973, -1.4859)
  line L1763 (94.6947, 65.0973, -1.4859) -> (94.8334, 64.9586, -1.4859)
  line L1764 (94.8334, 64.9586, -1.4859) -> (94.9487, 64.7999, -1.4859)
  line L1765 (94.9487, 64.7999, -1.4859) -> (94.9758, 64.7468, -1.4859)
  line L1766 (94.9758, 64.7468, -1.4859) -> (97.7545, 64.7468, -1.4859)
  line L1767 (97.7545, 64.7468, -1.4859) -> (101.3037, 68.2959, -1.4859)
  line L1768 (101.3037, 68.2959, -1.4859) -> (101.2969, 68.3387, -1.4859)
  line L1769 (101.2969, 68.3387, -1.4859) -> (101.293, 68.4367, -1.4859)
  line L1770 (101.293, 68.4367, -1.4859) -> (101.293, 68.9367, -1.4859)
  line L1771 (101.293, 68.9367, -1.4859) -> (101.2969, 69.0348, -1.4859)
  line L1772 (101.2969, 69.0348, -1.4859) -> (101.3276, 69.2285, -1.4859)
  line L1773 (101.3276, 69.2285, -1.4859) -> (101.3882, 69.4151, -1.4859)
  line L1774 (101.3882, 69.4151, -1.4859) -> (101.4772, 69.5899, -1.4859)
  line L1775 (101.4772, 69.5899, -1.4859) -> (101.5925, 69.7485, -1.4859)
  line L1776 (101.5925, 69.7485, -1.4859) -> (101.7312, 69.8872, -1.4859)
  line L1777 (101.7312, 69.8872, -1.4859) -> (101.8899, 70.0025, -1.4859)
  line L1778 (101.8899, 70.0025, -1.4859) -> (102.0647, 70.0916, -1.4859)
  line L1779 (102.0647, 70.0916, -1.4859) -> (102.2512, 70.1522, -1.4859)
  line L1780 (102.2512, 70.1522, -1.4859) -> (102.445, 70.1829, -1.4859)
  line L1781 (102.445, 70.1829, -1.4859) -> (102.6411, 70.1829, -1.4859)
  line L1782 (102.6411, 70.1829, -1.4859) -> (102.8349, 70.1522, -1.4859)
  line L1783 (137.7599, 70.1522, -1.4859) -> (137.9464, 70.0916, -1.4859)
  line L1784 (137.9464, 70.0916, -1.4859) -> (138.1212, 70.0025, -1.4859)
  line L1785 (138.1212, 70.0025, -1.4859) -> (138.2799, 69.8872, -1.4859)
  line L1786 (138.2799, 69.8872, -1.4859) -> (138.4186, 69.7485, -1.4859)
  line L1787 (138.4186, 69.7485, -1.4859) -> (138.5338, 69.5899, -1.4859)
  line L1788 (138.5338, 69.5899, -1.4859) -> (138.6229, 69.4151, -1.4859)
  line L1789 (138.6229, 69.4151, -1.4859) -> (138.6835, 69.2285, -1.4859)
  line L1790 (138.6835, 69.2285, -1.4859) -> (138.7142, 69.0348, -1.4859)
  line L1791 (138.7142, 69.0348, -1.4859) -> (138.718, 68.9367, -1.4859)
  line L1792 (138.718, 68.9367, -1.4859) -> (138.718, 68.4367, -1.4859)
  line L1793 (138.718, 68.4367, -1.4859) -> (138.7142, 68.3387, -1.4859)
  line L1794 (138.7142, 68.3387, -1.4859) -> (138.6835, 68.1449, -1.4859)
  line L1795 (138.6835, 68.1449, -1.4859) -> (138.6229, 67.9584, -1.4859)
  line L1796 (138.6229, 67.9584, -1.4859) -> (138.5338, 67.7836, -1.4859)
  line L1797 (138.5338, 67.7836, -1.4859) -> (138.4186, 67.6249, -1.4859)
  line L1798 (138.4186, 67.6249, -1.4859) -> (138.2799, 67.4862, -1.4859)
  line L1799 (138.2799, 67.4862, -1.4859) -> (138.1212, 67.3709, -1.4859)
  line L1800 (138.1212, 67.3709, -1.4859) -> (137.9464, 67.2819, -1.4859)
  line L1801 (137.9464, 67.2819, -1.4859) -> (137.7599, 67.2213, -1.4859)
  line L1802 (137.7599, 67.2213, -1.4859) -> (137.5661, 67.1906, -1.4859)
  line L1803 (137.5661, 67.1906, -1.4859) -> (137.37, 67.1906, -1.4859)
  line L1804 (137.37, 67.1906, -1.4859) -> (137.1762, 67.2213, -1.4859)
  line L1805 (137.1762, 67.2213, -1.4859) -> (136.9897, 67.2819, -1.4859)
  line L1806 (136.9897, 67.2819, -1.4859) -> (136.938, 67.3082, -1.4859)
  line L1807 (136.938, 67.3082, -1.4859) -> (133.3523, 63.7225, -1.4859)
  line L1808 (133.3523, 63.7225, -1.4859) -> (133.2933, 63.6708, -1.4859)
  line L1809 (133.2933, 63.6708, -1.4859) -> (133.1577, 63.5924, -1.4859)
  line L1810 (133.1577, 63.5924, -1.4859) -> (133.0064, 63.5519, -1.4859)
  line L1811 (133.0064, 63.5519, -1.4859) -> (132.9281, 63.5468, -1.4859)
  line L1812 (132.9281, 63.5468, -1.4859) -> (129.9008, 63.5468, -1.4859)
  line L1813 (129.9008, 63.5468, -1.4859) -> (129.8737, 63.4936, -1.4859)
  line L1814 (129.8737, 63.4936, -1.4859) -> (129.7584, 63.335, -1.4859)
  line L1815 (129.7584, 63.335, -1.4859) -> (129.6197, 63.1963, -1.4859)
  line L1816 (129.6197, 63.1963, -1.4859) -> (129.461, 63.081, -1.4859)
  line L1817 (129.461, 63.081, -1.4859) -> (129.2862, 62.9919, -1.4859)
  line L1818 (129.2862, 62.9919, -1.4859) -> (129.1579, 62.9502, -1.4859)
  line L1819 (129.1579, 62.9502, -1.4859) -> (129.1579, 59.6133, -1.4859)
  line L1820 (129.1579, 59.6133, -1.4859) -> (129.1528, 59.535, -1.4859)
  line L1821 (129.1528, 59.535, -1.4859) -> (129.1122, 59.3837, -1.4859)
  line L1822 (129.1122, 59.3837, -1.4859) -> (129.0339, 59.2481, -1.4859)
  line L1823 (129.0339, 59.2481, -1.4859) -> (128.9822, 59.1891, -1.4859)
  line L1824 (128.9822, 59.1891, -1.4859) -> (125.4319, 55.6388, -1.4859)
  line L1825 (125.4319, 55.6388, -1.4859) -> (125.4319, 46.29, -1.4859)
  line L1826 (125.4319, 46.29, -1.4859) -> (125.4268, 46.2116, -1.4859)
  line L1827 (125.4268, 46.2116, -1.4859) -> (125.3863, 46.0604, -1.4859)
  line L1828 (125.3863, 46.0604, -1.4859) -> (125.3079, 45.9247, -1.4859)
  line L1829 (125.3079, 45.9247, -1.4859) -> (125.2562, 45.8657, -1.4859)
  line L1830 (125.2562, 45.8657, -1.4859) -> (122.0408, 42.6503, -1.4859)
  line L1831 (122.0408, 42.6503, -1.4859) -> (122.0408, 40.7738, -1.4859)
  line L1832 (122.0408, 40.7738, -1.4859) -> (119.5908, 40.7738, -1.4859)
  line L1833 (119.5908, 40.7738, -1.4859) -> (119.5908, 43.7738, -1.4859)
  line L1834 (119.5908, 43.7738, -1.4859) -> (121.4673, 43.7738, -1.4859)
  line L1835 (121.4673, 43.7738, -1.4859) -> (124.2319, 46.5385, -1.4859)
  line L1836 (124.2319, 46.5385, -1.4859) -> (124.2319, 55.8874, -1.4859)
  line L1837 (124.2319, 55.8874, -1.4859) -> (124.2371, 55.9657, -1.4859)
  line L1838 (124.2371, 55.9657, -1.4859) -> (124.2776, 56.117, -1.4859)
  line L1839 (124.2776, 56.117, -1.4859) -> (124.3559, 56.2526, -1.4859)
  line L1840 (124.3559, 56.2526, -1.4859) -> (124.4077, 56.3116, -1.4859)
  line L1841 (124.4077, 56.3116, -1.4859) -> (127.9579, 59.8619, -1.4859)
  line L1842 (127.9579, 59.8619, -1.4859) -> (127.9579, 62.9502, -1.4859)
  line L1843 (127.9579, 62.9502, -1.4859) -> (127.8295, 62.9919, -1.4859)
  line L1844 (127.8295, 62.9919, -1.4859) -> (127.6548, 63.081, -1.4859)
  line L1845 (127.6548, 63.081, -1.4859) -> (127.4961, 63.1963, -1.4859)
  line L1846 (127.4961, 63.1963, -1.4859) -> (127.3574, 63.335, -1.4859)
  line L1847 (127.3574, 63.335, -1.4859) -> (127.2421, 63.4936, -1.4859)
  line L1848 (127.2421, 63.4936, -1.4859) -> (127.153, 63.6684, -1.4859)
  line L1849 (127.153, 63.6684, -1.4859) -> (127.0924, 63.855, -1.4859)
  line L1850 (127.0924, 63.855, -1.4859) -> (127.0617, 64.0487, -1.4859)
  line L1851 (127.0617, 64.0487, -1.4859) -> (127.0617, 64.2448, -1.4859)
  line L1852 (127.0617, 64.2448, -1.4859) -> (127.0924, 64.4386, -1.4859)
  line L1853 (127.0924, 64.4386, -1.4859) -> (127.153, 64.6251, -1.4859)
  line L1854 (127.153, 64.6251, -1.4859) -> (127.2421, 64.7999, -1.4859)
  line L1855 (127.2421, 64.7999, -1.4859) -> (127.3574, 64.9586, -1.4859)
  line L1856 (127.3574, 64.9586, -1.4859) -> (127.4961, 65.0973, -1.4859)
  line L1857 (127.4961, 65.0973, -1.4859) -> (127.6548, 65.2126, -1.4859)
  line L1858 (127.6548, 65.2126, -1.4859) -> (127.8295, 65.3016, -1.4859)
  line L1859 (127.8295, 65.3016, -1.4859) -> (128.0161, 65.3622, -1.4859)
  line L1860 (128.0161, 65.3622, -1.4859) -> (128.2098, 65.3929, -1.4859)
  line L1861 (128.2098, 65.3929, -1.4859) -> (128.3079, 65.3968, -1.4859)
  line L1862 (128.3079, 65.3968, -1.4859) -> (128.8079, 65.3968, -1.4859)
  line L1863 (128.8079, 65.3968, -1.4859) -> (128.906, 65.3929, -1.4859)
  line L1864 (128.906, 65.3929, -1.4859) -> (129.0997, 65.3622, -1.4859)
  line L1865 (129.0997, 65.3622, -1.4859) -> (129.2862, 65.3016, -1.4859)
  line L1866 (129.2862, 65.3016, -1.4859) -> (129.461, 65.2126, -1.4859)
  line L1867 (129.461, 65.2126, -1.4859) -> (129.6197, 65.0973, -1.4859)
  line L1868 (129.6197, 65.0973, -1.4859) -> (129.7584, 64.9586, -1.4859)
  line L1869 (129.7584, 64.9586, -1.4859) -> (129.8737, 64.7999, -1.4859)
  line L1870 (129.8737, 64.7999, -1.4859) -> (129.9008, 64.7468, -1.4859)
  line L1871 (129.9008, 64.7468, -1.4859) -> (132.6795, 64.7468, -1.4859)
  line L1872 (132.6795, 64.7468, -1.4859) -> (136.2287, 68.2959, -1.4859)
  line L1873 (136.2287, 68.2959, -1.4859) -> (136.2219, 68.3387, -1.4859)
  line L1874 (136.2219, 68.3387, -1.4859) -> (136.218, 68.4367, -1.4859)
  line L1875 (136.218, 68.4367, -1.4859) -> (136.218, 68.9367, -1.4859)
  line L1876 (136.218, 68.9367, -1.4859) -> (136.2219, 69.0348, -1.4859)
  line L1877 (136.2219, 69.0348, -1.4859) -> (136.2526, 69.2285, -1.4859)
  line L1878 (136.2526, 69.2285, -1.4859) -> (136.3132, 69.4151, -1.4859)
  line L1879 (136.3132, 69.4151, -1.4859) -> (136.4022, 69.5899, -1.4859)
  line L1880 (136.4022, 69.5899, -1.4859) -> (136.5175, 69.7485, -1.4859)
  line L1881 (136.5175, 69.7485, -1.4859) -> (136.6562, 69.8872, -1.4859)
  line L1882 (136.6562, 69.8872, -1.4859) -> (136.8149, 70.0025, -1.4859)
  line L1883 (136.8149, 70.0025, -1.4859) -> (136.9897, 70.0916, -1.4859)
  line L1884 (136.9897, 70.0916, -1.4859) -> (137.1762, 70.1522, -1.4859)
  line L1885 (137.1762, 70.1522, -1.4859) -> (137.37, 70.1829, -1.4859)
  line L1886 (137.37, 70.1829, -1.4859) -> (137.5661, 70.1829, -1.4859)
  line L1887 (137.5661, 70.1829, -1.4859) -> (137.7599, 70.1522, -1.4859)
  line L1888 (13.7868, 43.74, -1.4859) -> (13.9696, 43.6806, -1.4859)
  line L1889 (13.9696, 43.6806, -1.4859) -> (14.1409, 43.5933, -1.4859)
  line L1890 (14.1409, 43.5933, -1.4859) -> (14.2964, 43.4803, -1.4859)
  line L1891 (14.2964, 43.4803, -1.4859) -> (14.4323, 43.3444, -1.4859)
  line L1892 (14.4323, 43.3444, -1.4859) -> (14.5453, 43.1889, -1.4859)
  line L1893 (14.5453, 43.1889, -1.4859) -> (14.6326, 43.0176, -1.4859)
  line L1894 (14.6326, 43.0176, -1.4859) -> (14.692, 42.8348, -1.4859)
  line L1895 (14.692, 42.8348, -1.4859) -> (14.722, 42.6449, -1.4859)
  line L1896 (14.722, 42.6449, -1.4859) -> (14.7258, 42.5488, -1.4859)
  line L1897 (14.7258, 42.5488, -1.4859) -> (14.7258, 41.9988, -1.4859)
  line L1898 (14.7258, 41.9988, -1.4859) -> (14.722, 41.9027, -1.4859)
  line L1899 (14.722, 41.9027, -1.4859) -> (14.692, 41.7129, -1.4859)
  line L1900 (14.692, 41.7129, -1.4859) -> (14.6326, 41.53, -1.4859)
  line L1901 (14.6326, 41.53, -1.4859) -> (14.5453, 41.3588, -1.4859)
  line L1902 (14.5453, 41.3588, -1.4859) -> (14.4323, 41.2033, -1.4859)
  line L1903 (14.4323, 41.2033, -1.4859) -> (14.2964, 41.0673, -1.4859)
  line L1904 (14.2964, 41.0673, -1.4859) -> (14.1409, 40.9544, -1.4859)
  line L1905 (14.1409, 40.9544, -1.4859) -> (13.9696, 40.8671, -1.4859)
  line L1906 (13.9696, 40.8671, -1.4859) -> (13.7868, 40.8077, -1.4859)
  line L1907 (13.7868, 40.8077, -1.4859) -> (13.5969, 40.7776, -1.4859)
  line L1908 (13.5969, 40.7776, -1.4859) -> (13.4047, 40.7776, -1.4859)
  line L1909 (13.4047, 40.7776, -1.4859) -> (13.2148, 40.8077, -1.4859)
  line L1910 (13.2148, 40.8077, -1.4859) -> (13.032, 40.8671, -1.4859)
  line L1911 (13.032, 40.8671, -1.4859) -> (12.8607, 40.9544, -1.4859)
  line L1912 (12.8607, 40.9544, -1.4859) -> (12.7052, 41.0673, -1.4859)
  line L1913 (12.7052, 41.0673, -1.4859) -> (12.5693, 41.2033, -1.4859)
  line L1914 (12.5693, 41.2033, -1.4859) -> (12.4563, 41.3588, -1.4859)
  line L1915 (12.4563, 41.3588, -1.4859) -> (12.369, 41.53, -1.4859)
  line L1916 (12.369, 41.53, -1.4859) -> (12.3096, 41.7129, -1.4859)
  line L1917 (12.3096, 41.7129, -1.4859) -> (12.2796, 41.9027, -1.4859)
  line L1918 (12.2796, 41.9027, -1.4859) -> (12.2758, 41.9988, -1.4859)
  line L1919 (12.2758, 41.9988, -1.4859) -> (12.2758, 42.5488, -1.4859)
  line L1920 (12.2758, 42.5488, -1.4859) -> (12.2796, 42.6449, -1.4859)
  line L1921 (12.2796, 42.6449, -1.4859) -> (12.3096, 42.8348, -1.4859)
  line L1922 (12.3096, 42.8348, -1.4859) -> (12.369, 43.0176, -1.4859)
  line L1923 (12.369, 43.0176, -1.4859) -> (12.4563, 43.1889, -1.4859)
  line L1924 (12.4563, 43.1889, -1.4859) -> (12.5693, 43.3444, -1.4859)
  line L1925 (12.5693, 43.3444, -1.4859) -> (12.7052, 43.4803, -1.4859)
  line L1926 (12.7052, 43.4803, -1.4859) -> (12.8607, 43.5933, -1.4859)
  line L1927 (12.8607, 43.5933, -1.4859) -> (13.032, 43.6806, -1.4859)
  line L1928 (13.032, 43.6806, -1.4859) -> (13.2148, 43.74, -1.4859)
  line L1929 (13.2148, 43.74, -1.4859) -> (13.4047, 43.7701, -1.4859)
  line L1930 (13.4047, 43.7701, -1.4859) -> (13.5969, 43.7701, -1.4859)
  line L1931 (13.5969, 43.7701, -1.4859) -> (13.7868, 43.74, -1.4859)
  line L1932 (48.7118, 43.74, -1.4859) -> (48.8946, 43.6806, -1.4859)
  line L1933 (48.8946, 43.6806, -1.4859) -> (49.0659, 43.5933, -1.4859)
  line L1934 (49.0659, 43.5933, -1.4859) -> (49.2214, 43.4803, -1.4859)
  line L1935 (49.2214, 43.4803, -1.4859) -> (49.3573, 43.3444, -1.4859)
  line L1936 (49.3573, 43.3444, -1.4859) -> (49.4703, 43.1889, -1.4859)
  line L1937 (49.4703, 43.1889, -1.4859) -> (49.5576, 43.0176, -1.4859)
  line L1938 (49.5576, 43.0176, -1.4859) -> (49.617, 42.8348, -1.4859)
  line L1939 (49.617, 42.8348, -1.4859) -> (49.647, 42.6449, -1.4859)
  line L1940 (49.647, 42.6449, -1.4859) -> (49.6508, 42.5488, -1.4859)
  line L1941 (49.6508, 42.5488, -1.4859) -> (49.6508, 41.9988, -1.4859)
  line L1942 (49.6508, 41.9988, -1.4859) -> (49.647, 41.9027, -1.4859)
  line L1943 (49.647, 41.9027, -1.4859) -> (49.617, 41.7129, -1.4859)
  line L1944 (49.617, 41.7129, -1.4859) -> (49.5576, 41.53, -1.4859)
  line L1945 (49.5576, 41.53, -1.4859) -> (49.4703, 41.3588, -1.4859)
  line L1946 (49.4703, 41.3588, -1.4859) -> (49.3573, 41.2033, -1.4859)
  line L1947 (49.3573, 41.2033, -1.4859) -> (49.2214, 41.0673, -1.4859)
  line L1948 (49.2214, 41.0673, -1.4859) -> (49.0659, 40.9544, -1.4859)
  line L1949 (49.0659, 40.9544, -1.4859) -> (48.8946, 40.8671, -1.4859)
  line L1950 (48.8946, 40.8671, -1.4859) -> (48.7118, 40.8077, -1.4859)
  line L1951 (48.7118, 40.8077, -1.4859) -> (48.5219, 40.7776, -1.4859)
  line L1952 (48.5219, 40.7776, -1.4859) -> (48.3297, 40.7776, -1.4859)
  line L1953 (48.3297, 40.7776, -1.4859) -> (48.1398, 40.8077, -1.4859)
  line L1954 (48.1398, 40.8077, -1.4859) -> (47.957, 40.8671, -1.4859)
  line L1955 (47.957, 40.8671, -1.4859) -> (47.7857, 40.9544, -1.4859)
  line L1956 (47.7857, 40.9544, -1.4859) -> (47.6302, 41.0673, -1.4859)
  line L1957 (47.6302, 41.0673, -1.4859) -> (47.4943, 41.2033, -1.4859)
  line L1958 (47.4943, 41.2033, -1.4859) -> (47.3813, 41.3588, -1.4859)
  line L1959 (47.3813, 41.3588, -1.4859) -> (47.294, 41.53, -1.4859)
  line L1960 (47.294, 41.53, -1.4859) -> (47.2346, 41.7129, -1.4859)
  line L1961 (47.2346, 41.7129, -1.4859) -> (47.2046, 41.9027, -1.4859)
  line L1962 (47.2046, 41.9027, -1.4859) -> (47.2008, 41.9988, -1.4859)
  line L1963 (47.2008, 41.9988, -1.4859) -> (47.2008, 42.5488, -1.4859)
  line L1964 (47.2008, 42.5488, -1.4859) -> (47.2046, 42.6449, -1.4859)
  line L1965 (47.2046, 42.6449, -1.4859) -> (47.2346, 42.8348, -1.4859)
  line L1966 (47.2346, 42.8348, -1.4859) -> (47.294, 43.0176, -1.4859)
  line L1967 (47.294, 43.0176, -1.4859) -> (47.3813, 43.1889, -1.4859)
  line L1968 (47.3813, 43.1889, -1.4859) -> (47.4943, 43.3444, -1.4859)